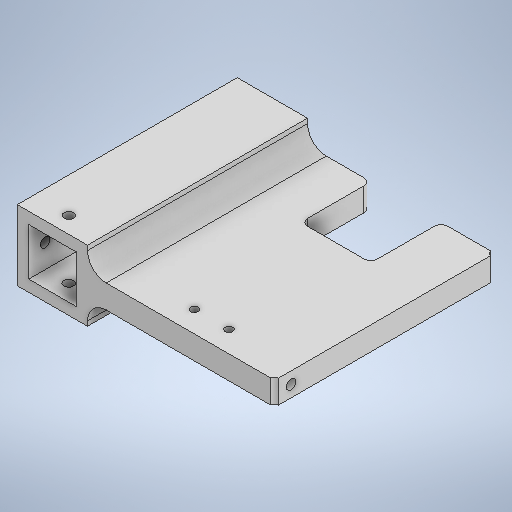
# Autodesk Inventor part: Agarre_Brazo
Saved by Autodesk Inventor 2025.3 (Build 293356030, 356C)
## iProperties
Created: 2025-08-20
Part Number: Agarre_Brazo
Material: Generic
Document SubType Name: Modeling
Designer: usuario
Density: 1 g/cm^3
Appearance: Default
Author: usuario
Autodesk Inventor part; units mm, degrees
ref_plane "YZ Plane" through (0, 0, 0) normal (1, 0, 0) x (0, 1, 0)
ref_plane "XZ Plane" through (0, 0, 0) normal (0, 1, 0) x (-1, 0, 0)
ref_plane "XY Plane" through (0, 0, 0) normal (0, 0, 1) x (1, 0, 0)
sketch "Sketch1" plane through (0, 0, 0) normal (0, 1, 0) x (-1, 0, 0)
  line L0 (15, -7) -> (-15, -7)
  line L1 (-15, -7) -> (-15, 7)
  line L2 (-15, 7) -> (15, 7)
  line L3 (15, 7) -> (15, -7)
  point P0 (0, 0)
  point P1 (-15, 0)
  point P2 (0, -7)
  dimension "d0" = 14
  dimension "d1" = 30
  constraints: 8 end point, 2 midpoint, 2 parallel, 1 horizontal, 1 horizontal alignment, 1 perpendicular, 1 vertical alignment
  measures "d0" distance of L0.end L1.end
  measures "d1" distance of L0.start L0.end
extrude "Extrusion1" add sketch "Sketch1" along normal blind 30
sketch "Sketch2" plane through (-15, 0, 7) normal (0, 0, 1) x (1, 0, 0)
  line L0 (4.9, 25.1) -> (25.1, 25.1)
  line L1 (25.1, 25.1) -> (25.1, 4.9)
  line L2 (25.1, 4.9) -> (4.9, 4.9)
  line L3 (4.9, 4.9) -> (4.9, 25.1)
  line L4 (0, 30) -> (30, 30) projected
  line L5 (0, 0) -> (30, 0) projected
  line L6 (30, 0) -> (30, 30) projected
  point P0 (15, 0)
  point P1 (15, 25.1)
  point P2 (15, 30)
  point P3 (30, 15)
  point P4 (25.1, 15)
  dimension "d6" = 20.2
  dimension "d27" = 20.2
  constraints: 8 end point, 4 midpoint, 2 parallel, 1 horizontal, 1 horizontal alignment, 1 perpendicular, 1 vertical alignment
  measures "d6" distance of L0.start L0.end
  measures "d27" distance of L0.end L1.end
extrude "Extrusion2" cut sketch "Sketch2" against normal up to surface (14 mm away)
sketch "Sketch3" plane through (15, 0, 7) normal (1, 0, 0) x (0, 0, -1)
  line L0 (0, 0) -> (14, 0) projected
  line L1 (0, 0) -> (0, 30) projected
  point P0 (7, 0)
  point P1 (7, 15)
  dimension "d9" = 15
  dimension "d17" = 7
  measures "d9" distance from line of L0 point (7, 15)
  measures "d17" distance from line of L1 point (7, 15)
hole "Hole1" at (15, 15, 0) direction (-1, 0, 0) diameter 4.1 end through all
sketch "Sketch4" plane through (0, 30, 0) normal (0, 1, 0) x (1, 0, 0)
  line L0 (15, -7) -> (15, 7) projected
  line L1 (-15, -7) -> (15, -7) projected
  point P0 (0, 0)
  point P1 (0, 0)
  dimension "d18" = 15
  dimension "d19" = 7
  measures "d18" distance from line of L0 point (0, 0)
  measures "d19" distance from line of L1 point (0, 0)
hole "Hole2" at (0, 30, 0) direction (0, -1, 0) diameter 4.1 end through all
sketch "Sketch5" plane through (15, 0, -7) normal (0, 0, -1) x (-1, 0, 0)
  line L0 (4.9, 4.9) -> (4.9, 25.1) projected
  line L1 (0, 0) -> (0, 30) projected
  line L2 (12.95, 4.9) -> (17.05, 4.9) projected
  line L3 (17.05, 0) -> (12.95, 0) projected
  line L4 (25.1, 12.95) -> (25.1, 17.05) projected
  line L5 (25.1, 12.95) -> (25.1, 17.05) projected
  line L6 (30, 17.05) -> (30, 12.95) projected
  line L7 (25.1, 4.9) -> (4.9, 4.9) projected
  line L8 (4.9, 4.9) -> (25.1, 4.9) projected
  line L9 (12.95, 4.9) -> (17.05, 4.9) projected
  line L10 (25.1, 4.9) -> (4.9, 4.9) projected
  line L11 (4.9, 4.9) -> (25.1, 4.9) projected
  line L12 (4.9, 25.1) -> (4.9, 4.9) projected
  line L13 (25.1, 4.9) -> (25.1, 25.1) projected
  line L14 (25.1, 25.1) -> (25.1, 4.9) projected
  line L15 (25.1, 12.95) -> (25.1, 17.05) projected
  line L16 (25.1, 25.1) -> (25.1, 4.9) projected
  line L17 (25.1, 4.9) -> (25.1, 25.1) projected
  line L18 (4.9, 17.05) -> (4.9, 12.95) projected
  line L19 (4.9, 4.9) -> (4.9, 25.1) projected
  line L20 (4.9, 25.1) -> (4.9, 4.9) projected
  line L21 (4.9, 25.1) -> (25.1, 25.1) projected
  line L22 (30, 0) -> (0, 0) projected
  line L23 (0, 0) -> (30, 0) projected
  line L24 (17.05, 25.1) -> (12.95, 25.1) projected
  line L25 (4.9, 25.1) -> (25.1, 25.1) projected
  line L26 (25.1, 25.1) -> (4.9, 25.1) projected
  line L27 (17.05, 0) -> (12.95, 0) projected
  line L28 (30, 0) -> (0, 0) projected
  line L29 (0, 0) -> (30, 0) projected
  line L30 (0, 0) -> (0, 30) projected
  line L31 (30, 0) -> (30, 30) projected
  line L32 (30, 0) -> (30, 30) projected
  line L33 (30, 17.05) -> (30, 12.95) projected
  line L34 (30, 0) -> (30, 30) projected
  line L35 (30, 0) -> (30, 30) projected
  line L36 (0, 12.95) -> (0, 17.05) projected
  line L37 (0, 0) -> (0, 30) projected
  line L38 (0, 0) -> (0, 30) projected
  line L39 (30, 30) -> (0, 30) projected
  line L40 (0, 30) -> (30, 30) projected
  line L41 (12.95, 30) -> (17.05, 30) projected
  line L42 (30, 30) -> (0, 30) projected
  line L43 (0, 30) -> (30, 30) projected
  line L44 (25.1, 25.1) -> (25.1, 4.9) projected
  line L45 (25.1, 4.9) -> (4.9, 4.9) projected
  line L46 (4.9, 4.9) -> (4.9, 25.1) projected
  line L47 (4.9, 25.1) -> (25.1, 25.1) projected
  line L48 (0, 0) -> (30, 0) projected
  line L49 (30, 0) -> (30, 30) projected
  line L50 (0, 30) -> (30, 30) projected
  line L51 (0, 0) -> (0, 30) projected
  line L52 (25.1, 4.9) -> (25.1, 25.1) projected
  line L53 (25.1, 25.1) -> (4.9, 25.1) projected
  line L54 (4.9, 25.1) -> (4.9, 4.9) projected
  line L55 (4.9, 4.9) -> (25.1, 4.9) projected
  line L56 (30, 0) -> (0, 0) projected
  line L57 (0, 0) -> (0, 30) projected
  line L58 (30, 30) -> (0, 30) projected
  line L59 (30, 0) -> (30, 30) projected
  line L60 (4.9, 17.05) -> (4.9, 12.95) projected
  line L61 (0, 12.95) -> (0, 17.05) projected
  line L62 (0, 12.95) -> (0, 17.05) projected
  line L63 (4.9, 17.05) -> (4.9, 12.95) projected
  line L64 (12.95, 4.9) -> (17.05, 4.9) projected
  line L65 (30, 17.05) -> (30, 12.95) projected
  line L66 (12.95, 30) -> (17.05, 30) projected
  line L67 (12.95, 30) -> (17.05, 30) projected
  line L68 (17.05, 25.1) -> (12.95, 25.1) projected
  line L69 (17.05, 25.1) -> (12.95, 25.1) projected
  line L70 (17.05, 0) -> (12.95, 0) projected
  line L71 (25.1, 25.1) -> (4.9, 25.1) projected
  point P0 (15, 0)
  constraints: 1 other
extrude "Extrusion3" add sketch "Sketch5" along normal blind 80
sketch "Sketch6" plane through (15, 0, 7) normal (1, 0, 0) x (0, 0, -1)
  circle A0 centre (7, 15) radius 2.05 projected
  circle A1 centre (7, 15) radius 2.05 projected
  circle A2 centre (7, 15) radius 2.05 projected
  circle A3 centre (7, 15) radius 2.05 projected
  line L0 (9.05, 25.1) -> (4.95, 25.1) projected
  line L1 (0, 25.1) -> (0, 4.9) projected
  line L2 (0, 4.9) -> (0, 25.1) projected
  line L3 (4.95, 30) -> (9.05, 30) projected
  line L4 (9.05, 25.1) -> (4.95, 25.1) projected
  line L5 (0, 0) -> (0, 30) projected
  line L6 (0, 0) -> (0, 30) projected
  line L7 (0, 4.9) -> (0, 25.1) projected
  line L8 (0, 25.1) -> (0, 4.9) projected
  line L9 (0, 0) -> (0, 30) projected
  line L10 (0, 0) -> (0, 30) projected
  line L11 (0, 4.9) -> (94, 4.9) projected
  line L12 (0, 4.9) -> (94, 4.9) projected
  line L13 (0, 0) -> (94, 0) projected
  line L14 (0, 0) -> (94, 0) projected
  line L15 (4.95, 4.9) -> (9.05, 4.9) projected
  line L16 (0, 4.9) -> (94, 4.9) projected
  line L17 (0, 4.9) -> (94, 4.9) projected
  line L18 (0, 25.1) -> (94, 25.1) projected
  circle A4 centre (7, 15) radius 2.05 projected
  line L19 (0, 4.9) -> (94, 4.9) projected
  line L20 (0, 25.1) -> (0, 4.9) projected
  line L21 (0, 25.1) -> (94, 25.1) projected
  line L22 (94, 4.9) -> (94, 25.1) projected
  line L23 (0, 25.1) -> (94, 25.1) projected
  circle A5 centre (7, 15) radius 2.05 projected
  line L24 (0, 25.1) -> (94, 25.1) projected
  line L25 (0, 4.9) -> (0, 25.1) projected
  line L26 (0, 4.9) -> (94, 4.9) projected
  line L27 (94, 25.1) -> (94, 4.9) projected
  line L28 (9.05, 0) -> (4.95, 0) projected
  line L29 (0, 0) -> (94, 0) projected
  line L30 (0, 0) -> (94, 0) projected
  line L31 (9.05, 25.1) -> (4.95, 25.1) projected
  line L32 (0, 25.1) -> (94, 25.1) projected
  line L33 (0, 25.1) -> (94, 25.1) projected
  line L34 (0, 30) -> (94, 30) projected
  circle A6 centre (7, 15) radius 2.05 projected
  line L35 (0, 0) -> (94, 0) projected
  line L36 (0, 0) -> (0, 30) projected
  line L37 (0, 30) -> (94, 30) projected
  line L38 (94, 0) -> (94, 30) projected
  line L39 (4.95, 30) -> (9.05, 30) projected
  line L40 (0, 30) -> (94, 30) projected
  line L41 (0, 30) -> (94, 30) projected
  line L42 (0, 30) -> (94, 30) projected
  circle A7 centre (7, 15) radius 2.05 projected
  line L43 (0, 0) -> (94, 0) projected
  line L44 (94, 30) -> (94, 0) projected
  line L45 (0, 30) -> (94, 30) projected
  line L46 (0, 0) -> (0, 30) projected
  line L47 (4.95, 4.9) -> (9.05, 4.9) projected
  line L48 (9.05, 0) -> (4.95, 0) projected
  line L49 (4.95, 4.9) -> (9.05, 4.9) projected
  line L50 (9.05, 0) -> (4.95, 0) projected
  line L51 (4.95, 30) -> (9.05, 30) projected
  circle A8 centre (7, 15) radius 2.05 projected
  circle A9 centre (7, 15) radius 2.05 projected
  circle A10 centre (7, 15) radius 2.05 projected
  circle A11 centre (7, 15) radius 2.05 projected
  line L52 (94, 30) -> (94, 0) projected
  line L53 (94, 25.1) -> (94, 4.9) projected
  line L54 (94, 30) -> (94, 0) projected
  line L55 (94, 0) -> (94, 30) projected
  line L56 (94, 25.1) -> (94, 4.9) projected
  line L57 (94, 4.9) -> (94, 25.1) projected
  line L58 (94, 0) -> (94, 30) projected
  line L59 (94, 4.9) -> (94, 25.1) projected
  line L60 (0, 20) -> (94, 20)
  line L61 (94, 20) -> (94, 10)
  line L62 (94, 10) -> (0, 10)
  line L63 (0, 10) -> (0, 20)
  point P0 (7, 0)
  point P1 (0, 10)
  point P2 (94, 10)
  point P3 (94, 20)
  dimension "d30" = 10
  dimension "d31" = 10
  constraints: 8 end point, 2 parallel, 1 horizontal, 1 perpendicular, 1 point on line, 7 other
  measures "d30" distance between parallel lines of L34 L60
  measures "d31" distance between parallel lines of L13 L62
extrude "Extrusion4" add sketch "Sketch6" along normal blind 80 contours L22 L62 L1 L60
fillet "Fillet1" radius 8 2 edges at (15, 20, -40) (15, 10, -40)
sketch "Sketch7" plane through (95, 20, 7) normal (0, 1, 0) x (1, 0, 0)
  line L0 (-72, 0) -> (0, 0) projected
  line L1 (0, 0) -> (0, 94) projected
  line L2 (-72, 94) -> (0, 94) projected
  line L3 (-72, 94) -> (0, 94) projected
  line L4 (0, 94) -> (0, 0) projected
  line L5 (-72, 0) -> (0, 0) projected
  line L6 (-105.1, 0) -> (-84.9, 0) projected
  line L7 (-84.9, 0) -> (-105.1, 0) projected
  line L8 (-110, 0) -> (-80, 0) projected
  line L9 (-72, 0) -> (-80, 0) projected
  line L10 (-72, 0) -> (0, 0) projected
  line L11 (-72, 0) -> (0, 0) projected
  line L12 (-80, 0) -> (-72, 0) projected
  line L13 (-110, 0) -> (-80, 0) projected
  line L14 (-72, 94) -> (-80, 94) projected
  line L15 (-72, 94) -> (0, 94) projected
  line L16 (-72, 94) -> (0, 94) projected
  line L17 (-80, 94) -> (-72, 94) projected
  line L18 (-80, 94) -> (-110, 94) projected
  line L19 (-110, 94) -> (-80, 94) projected
  line L20 (-84.9, 94) -> (-105.1, 94) projected
  line L21 (-105.1, 94) -> (-84.9, 94) projected
  line L22 (-72, 94) -> (-72, 0) projected
  line L23 (-72, 94) -> (0, 94) projected
  line L24 (0, 0) -> (0, 94) projected
  line L25 (-72, 0) -> (0, 0) projected
  line L26 (-72, 0) -> (-72, 94) projected
  line L27 (-72, 0) -> (0, 0) projected
  line L28 (0, 94) -> (0, 0) projected
  line L29 (-72, 94) -> (0, 94) projected
  line L30 (0, 9.05) -> (0, 4.95) projected
  line L31 (0, 94) -> (0, 0) projected
  line L32 (0, 0) -> (0, 94) projected
  line L33 (0, 9.05) -> (0, 4.95) projected
  line L34 (0, 9.05) -> (0, 4.95) projected
  line L35 (-84.9, 4.95) -> (-84.9, 9.05) projected
  line L36 (-84.9, 9.05) -> (0, 9.05) projected
  point P0 (-95, 7)
  point P1 (-43.366, 9.05)
  point P2 (-28.634, 9.05)
  point P3 (-36, 0)
  dimension "d35" = 14.732
  dimension "d36" = 7.366
  constraints: 1 midpoint, 1 point on line
  measures "d35" distance of point (-43.366, 9.05) point (-28.634, 9.05)
  measures "d36" horizontal distance of point (-36, 0) point (-43.366, 9.05)
hole "Hole3" at (95, 20, 7) at (95, 20, -87) at (51.634, 20, -2.05) at (66.366, 20, -2.05) direction (0, -1, 0) diameter 3.302 end through all
sketch "Sketch8" plane through (23, 20, 7) normal (0, 1, 0) x (1, 0, 0)
  line L0 (0, 94) -> (70.349, 94) projected
  line L1 (49.077, 94) -> (19.077, 94)
  line L2 (19.077, 94) -> (19.077, 64)
  line L3 (19.077, 64) -> (49.077, 64)
  line L4 (49.077, 64) -> (49.077, 94)
  point P0 (-23, 7)
  point P1 (19.077, 94)
  dimension "d44" = 30
  dimension "d45" = 30
  constraints: 8 end point, 2 parallel, 1 horizontal, 1 perpendicular, 1 point on line
  measures "d44" distance of L2.end L3.end
  measures "d45" distance of L1.end L2.end
extrude "Extrusion5" cut sketch "Sketch8" against normal through all
fillet "Fillet2" radius 3 2 edges at (72.077, 15, -57) (42.077, 15, -57)
body "Solid1"
